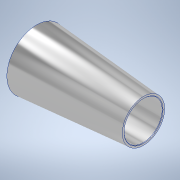
# Autodesk Inventor part: 1.1_6_SpacerA
Saved by Autodesk Inventor 2021 (Build 250183000, 183)
## iProperties
Created: 2025-11-22
Part Number: 1.1_6_SpacerA
Material: Aluminum 6061
Document SubType Name: Modeling
Designer: Admin
Density: 2.7 g/cm^3
Appearance: Aluminum - Flat
Author: Admin
Autodesk Inventor part; units mm, degrees
ref_plane "YZ Plane" through (0, 0, 0) normal (1, 0, 0) x (0, 1, 0)
ref_plane "XZ Plane" through (0, 0, 0) normal (0, 1, 0) x (-1, 0, 0)
ref_plane "XY Plane" through (0, 0, 0) normal (0, 0, 1) x (1, 0, 0)
sketch "Sketch1" plane through (0, 0, 0) normal (0, 1, 0) x (-1, 0, 0)
  line L0 (0, -9.1) -> (-51, -9.1)
  line L1 (-51, -9.1) -> (-51, -10.1)
  line L2 (-51, -10.1) -> (0, -14.1)
  line L3 (0, -14.1) -> (0, -9.1)
  line L4 (-61.2, 0) -> (10.2, 0) projected
  line L5 (0, -16.92) -> (0, 2.82) projected
  point P0 (0, 0)
  dimension "d0" = 9.1
  dimension "d1" = 5
  dimension "d2" = 1
  dimension "d3" = 51
  constraints: 8 end point, 1 collinear, 1 horizontal, 1 parallel, 1 perpendicular
  measures "d0" distance between parallel lines of L4 L0
  measures "d1" distance of L2.end L0.start
  measures "d2" distance of L0.end L1.end
  measures "d3" distance of L0.start L0.end
revolve "Revolution1" add sketch "Sketch1" angle 360 about axis through (0, 0, 0) along (-1, 0, 0)
chamfer "Chamfer1" distance 0.2 angle 45 2 edges at (51, 0, 9.1) (0, 0, 9.1)
body "Solid1"
